Autodesk Fusion 360 part; units mm, degrees
(part 3 of 7)
  spline S81 degree 5 poles (24.1275, 16.6487) (24.1224, 16.6501) (24.1069, 16.6547) (24.0809, 16.6621) (24.0445, 16.6725) (23.9974, 16.6854) (23.9449, 16.6996) (23.8923, 16.7134) (23.8395, 16.7269) (23.7865, 16.74) (23.7335, 16.7529) (23.6803, 16.7655) (23.6269, 16.7777) (23.5735, 16.7897) (23.5199, 16.8014) (23.4662, 16.8128) (23.4124, 16.8239) (23.3585, 16.8347) (23.3045, 16.8453) (23.2503, 16.8556) (23.1961, 16.8656) (23.1417, 16.8754) (23.0873, 16.8849) (23.0327, 16.8942) (22.9781, 16.9032) (22.9234, 16.9119) (22.8685, 16.9204) (22.8136, 16.9287) (22.7586, 16.9367) (22.7034, 16.9445) (22.6482, 16.952) (22.5929, 16.9593) (22.5376, 16.9664) (22.4821, 16.9732) (22.4266, 16.9798) (22.3709, 16.9861) (22.3152, 16.9923) (22.2594, 16.9982) (22.2036, 17.0039) (22.1476, 17.0093) (22.0916, 17.0146) (22.0355, 17.0196) (21.9794, 17.0244) (21.9231, 17.029) (21.8668, 17.0334) (21.8104, 17.0375) (21.754, 17.0415) (21.6975, 17.0452) (21.6409, 17.0487) (21.5842, 17.052) (21.5275, 17.0551) (21.4707, 17.058) (21.4139, 17.0607) (21.357, 17.0632) (21.3, 17.0655) (21.243, 17.0675) (21.1973, 17.069) (21.163, 17.0701) (21.1402, 17.0707) (21.1287, 17.071) knots 0.221564 0.221564 0.221564 0.221564 0.221564 0.221564 0.228571 0.242857 0.257143 0.271429 0.285714 0.3 0.314286 0.328571 0.342857 0.357143 0.371429 0.385714 0.4 0.414286 0.428571 0.442857 0.457143 0.471429 0.485714 0.5 0.514286 0.528571 0.542857 0.557143 0.571429 0.585714 0.6 0.614286 0.628571 0.642857 0.657143 0.671429 0.685714 0.7 0.714286 0.728571 0.742857 0.757143 0.771429 0.785714 0.8 0.814286 0.828571 0.842857 0.857143 0.871429 0.885714 0.9 0.914286 0.928571 0.942857 0.957143 0.971429 0.985714 1 1 1 1 1 1
  arc A41 (21.1287, 17.071) -> (20.616, 16.0313) centre (54.5011, -0.0327) ccw
  spline S82 degree 5 poles (20.616, 16.0313) (20.6232, 16.0224) (20.6376, 16.0046) (20.6593, 15.9781) (20.6883, 15.9427) (20.7247, 15.8987) (20.7612, 15.8549) (20.7978, 15.8113) (20.8345, 15.7678) (20.8714, 15.7246) (20.9083, 15.6815) (20.9455, 15.6385) (20.9827, 15.5958) (21.0201, 15.5532) (21.0576, 15.5108) (21.0952, 15.4686) (21.1329, 15.4266) (21.1708, 15.3848) (21.2088, 15.3432) (21.2469, 15.3017) (21.2852, 15.2605) (21.3236, 15.2194) (21.3621, 15.1786) (21.4007, 15.1379) (21.4395, 15.0974) (21.4784, 15.0572) (21.5175, 15.0171) (21.5567, 14.9773) (21.596, 14.9376) (21.6354, 14.8982) (21.675, 14.859) (21.7147, 14.82) (21.7546, 14.7812) (21.7946, 14.7427) (21.8347, 14.7044) (21.875, 14.6662) (21.9154, 14.6284) (21.9559, 14.5907) (21.9966, 14.5533) (22.0375, 14.5162) (22.0784, 14.4792) (22.1196, 14.4426) (22.1608, 14.4061) (22.2023, 14.3699) (22.2438, 14.334) (22.2856, 14.2984) (22.3274, 14.263) (22.3695, 14.2279) (22.4117, 14.193) (22.454, 14.1585) (22.4965, 14.1242) (22.5392, 14.0902) (22.5821, 14.0565) (22.6251, 14.0232) (22.6682, 13.9901) (22.7072, 13.9607) (22.7376, 13.938) (22.7593, 13.922) (22.7723, 13.9124) (22.7766, 13.9093) knots -1 -1 -1 -1 -1 -1 -0.985714 -0.971429 -0.957143 -0.942857 -0.928571 -0.914286 -0.9 -0.885714 -0.871429 -0.857143 -0.842857 -0.828571 -0.814286 -0.8 -0.785714 -0.771429 -0.757143 -0.742857 -0.728571 -0.714286 -0.7 -0.685714 -0.671429 -0.657143 -0.642857 -0.628571 -0.614286 -0.6 -0.585714 -0.571429 -0.557143 -0.542857 -0.528571 -0.514286 -0.5 -0.485714 -0.471429 -0.457143 -0.442857 -0.428571 -0.414286 -0.4 -0.385714 -0.371429 -0.357143 -0.342857 -0.328571 -0.314286 -0.3 -0.285714 -0.271429 -0.257143 -0.242857 -0.228571 -0.221564 -0.221564 -0.221564 -0.221564 -0.221564 -0.221564
  spline S83 degree 3 poles (22.9417, 13.3112) (22.967, 13.3712) (22.9804, 13.4355) (22.9818, 13.5657) (22.9698, 13.6304) (22.9284, 13.7343) (22.9051, 13.775) (22.8479, 13.8489) (22.8143, 13.8817) (22.7766, 13.9093) knots 0 0 0 0 0.019532 0.019532 0.039064 0.039064 0.053081 0.053081 0.067098 0.067098 0.067098 0.067098
  arc A42 (22.9417, 13.3112) -> (22.7496, 12.8476) centre (54.5011, -0.0327) ccw
  spline S84 degree 3 poles (22.21, 12.5414) (22.2744, 12.5315) (22.34, 12.5342) (22.4666, 12.5647) (22.5263, 12.5921) (22.617, 12.6576) (22.6508, 12.6901) (22.7085, 12.7637) (22.7321, 12.8043) (22.7496, 12.8476) knots 0 0 0 0 0.019532 0.019532 0.039064 0.039064 0.053081 0.053081 0.067098 0.067098 0.067098 0.067098
  spline S85 degree 5 poles (22.21, 12.5414) (22.2048, 12.5422) (22.1888, 12.5447) (22.1621, 12.5487) (22.1246, 12.5542) (22.0762, 12.5609) (22.0223, 12.5681) (21.9683, 12.5749) (21.9142, 12.5813) (21.86, 12.5875) (21.8057, 12.5933) (21.7513, 12.5988) (21.6969, 12.604) (21.6423, 12.6089) (21.5877, 12.6135) (21.533, 12.6178) (21.4782, 12.6218) (21.4233, 12.6255) (21.3683, 12.6289) (21.3133, 12.6321) (21.2582, 12.6349) (21.2031, 12.6375) (21.1479, 12.6399) (21.0926, 12.6419) (21.0372, 12.6437) (20.9818, 12.6452) (20.9263, 12.6465) (20.8708, 12.6475) (20.8152, 12.6483) (20.7595, 12.6488) (20.7038, 12.6491) (20.648, 12.6491) (20.5922, 12.6488) (20.5363, 12.6484) (20.4804, 12.6477) (20.4244, 12.6467) (20.3684, 12.6455) (20.3123, 12.6441) (20.2562, 12.6425) (20.2, 12.6406) (20.1438, 12.6385) (20.0875, 12.6361) (20.0312, 12.6336) (19.9748, 12.6308) (19.9184, 12.6277) (19.862, 12.6245) (19.8055, 12.621) (19.749, 12.6174) (19.6924, 12.6135) (19.6358, 12.6094) (19.5792, 12.605) (19.5225, 12.6005) (19.4658, 12.5957) (19.4091, 12.5908) (19.3523, 12.5856) (19.2955, 12.5802) (19.25, 12.5757) (19.2159, 12.5723) (19.1931, 12.5699) (19.1818, 12.5687) knots 0.221564 0.221564 0.221564 0.221564 0.221564 0.221564 0.228571 0.242857 0.257143 0.271429 0.285714 0.3 0.314286 0.328571 0.342857 0.357143 0.371429 0.385714 0.4 0.414286 0.428571 0.442857 0.457143 0.471429 0.485714 0.5 0.514286 0.528571 0.542857 0.557143 0.571429 0.585714 0.6 0.614286 0.628571 0.642857 0.657143 0.671429 0.685714 0.7 0.714286 0.728571 0.742857 0.757143 0.771429 0.785714 0.8 0.814286 0.828571 0.842857 0.857143 0.871429 0.885714 0.9 0.914286 0.928571 0.942857 0.957143 0.971429 0.985714 1 1 1 1 1 1
  arc A43 (19.1818, 12.5687) -> (18.8091, 11.4709) centre (54.5011, -0.0327) ccw
  spline S86 degree 5 poles (18.8091, 11.4709) (18.8174, 11.4631) (18.834, 11.4474) (18.859, 11.4238) (18.8924, 11.3926) (18.9342, 11.3537) (18.976, 11.3151) (19.018, 11.2766) (19.0601, 11.2383) (19.1023, 11.2002) (19.1446, 11.1623) (19.187, 11.1246) (19.2295, 11.087) (19.2721, 11.0497) (19.3148, 11.0126) (19.3576, 10.9757) (19.4005, 10.9389) (19.4435, 10.9024) (19.4867, 10.8661) (19.5299, 10.83) (19.5732, 10.7941) (19.6166, 10.7584) (19.6601, 10.7229) (19.7038, 10.6876) (19.7475, 10.6526) (19.7913, 10.6178) (19.8353, 10.5832) (19.8793, 10.5488) (19.9235, 10.5146) (19.9677, 10.4807) (20.0121, 10.447) (20.0565, 10.4135) (20.1011, 10.3802) (20.1458, 10.3472) (20.1906, 10.3145) (20.2355, 10.2819) (20.2805, 10.2497) (20.3256, 10.2176) (20.3708, 10.1859) (20.4162, 10.1543) (20.4616, 10.1231) (20.5072, 10.0921) (20.5529, 10.0613) (20.5987, 10.0309) (20.6446, 10.0007) (20.6906, 9.9708) (20.7367, 9.9412) (20.783, 9.9118) (20.8294, 9.8828) (20.8759, 9.8541) (20.9225, 9.8257) (20.9692, 9.7975) (21.0161, 9.7697) (21.0631, 9.7422) (21.1102, 9.7151) (21.1527, 9.691) (21.1857, 9.6726) (21.2094, 9.6595) (21.2236, 9.6517) (21.2282, 9.6492) knots -1 -1 -1 -1 -1 -1 -0.985714 -0.971429 -0.957143 -0.942857 -0.928571 -0.914286 -0.9 -0.885714 -0.871429 -0.857143 -0.842857 -0.828571 -0.814286 -0.8 -0.785714 -0.771429 -0.757143 -0.742857 -0.728571 -0.714286 -0.7 -0.685714 -0.671429 -0.657143 -0.642857 -0.628571 -0.614286 -0.6 -0.585714 -0.571429 -0.557143 -0.542857 -0.528571 -0.514286 -0.5 -0.485714 -0.471429 -0.457143 -0.442857 -0.428571 -0.414286 -0.4 -0.385714 -0.371429 -0.357143 -0.342857 -0.328571 -0.314286 -0.3 -0.285714 -0.271429 -0.257143 -0.242857 -0.228571 -0.221564 -0.221564 -0.221564 -0.221564 -0.221564 -0.221564
  spline S87 degree 3 poles (21.4699, 9.0777) (21.4872, 9.1405) (21.4921, 9.206) (21.4765, 9.3353) (21.4561, 9.3978) (21.4016, 9.4954) (21.3732, 9.5328) (21.3068, 9.5986) (21.2692, 9.6267) (21.2282, 9.6492) knots 0 0 0 0 0.019532 0.019532 0.039064 0.039064 0.053081 0.053081 0.067098 0.067098 0.067098 0.067098
  arc A44 (21.4699, 9.0777) -> (21.3401, 8.593) centre (54.5011, -0.0327) ccw
  spline S88 degree 3 poles (20.845, 8.219) (20.9101, 8.2175) (20.9749, 8.2288) (21.0964, 8.2756) (21.152, 8.3106) (21.2333, 8.3873) (21.2627, 8.424) (21.3102, 8.5044) (21.3283, 8.5478) (21.3401, 8.593) knots 0 0 0 0 0.019532 0.019532 0.039064 0.039064 0.053081 0.053081 0.067098 0.067098 0.067098 0.067098
  spline S89 degree 5 poles (20.845, 8.219) (20.8397, 8.2191) (20.8235, 8.2195) (20.7965, 8.22) (20.7586, 8.2205) (20.7099, 8.2209) (20.6555, 8.2209) (20.601, 8.2206) (20.5465, 8.22) (20.492, 8.219) (20.4374, 8.2177) (20.3828, 8.2161) (20.3281, 8.2141) (20.2734, 8.2118) (20.2186, 8.2093) (20.1638, 8.2064) (20.1089, 8.2032) (20.054, 8.1997) (19.9991, 8.1959) (19.9442, 8.1919) (19.8892, 8.1875) (19.8341, 8.1829) (19.7791, 8.178) (19.724, 8.1728) (19.6689, 8.1673) (19.6137, 8.1616) (19.5586, 8.1557) (19.5034, 8.1494) (19.4481, 8.1429) (19.3929, 8.1361) (19.3376, 8.1291) (19.2823, 8.1219) (19.227, 8.1144) (19.1717, 8.1066) (19.1163, 8.0986) (19.0609, 8.0903) (19.0055, 8.0819) (18.9501, 8.0731) (18.8947, 8.0642) (18.8392, 8.055) (18.7838, 8.0455) (18.7283, 8.0359) (18.6728, 8.026) (18.6173, 8.0158) (18.5618, 8.0055) (18.5062, 7.9949) (18.4507, 7.9841) (18.3951, 7.9731) (18.3396, 7.9618) (18.284, 7.9504) (18.2284, 7.9387) (18.1728, 7.9268) (18.1172, 7.9147) (18.0616, 7.9023) (18.006, 7.8898) (17.9504, 7.877) (17.9059, 7.8667) (17.8725, 7.8588) (17.8502, 7.8535) (17.8391, 7.8508) knots 0.221564 0.221564 0.221564 0.221564 0.221564 0.221564 0.228571 0.242857 0.257143 0.271429 0.285714 0.3 0.314286 0.328571 0.342857 0.357143 0.371429 0.385714 0.4 0.414286 0.428571 0.442857 0.457143 0.471429 0.485714 0.5 0.514286 0.528571 0.542857 0.557143 0.571429 0.585714 0.6 0.614286 0.628571 0.642857 0.657143 0.671429 0.685714 0.7 0.714286 0.728571 0.742857 0.757143 0.771429 0.785714 0.8 0.814286 0.828571 0.842857 0.857143 0.871429 0.885714 0.9 0.914286 0.928571 0.942857 0.957143 0.971429 0.985714 1 1 1 1 1 1
  arc A45 (17.8391, 7.8508) -> (17.6129, 6.7138) centre (54.5011, -0.0327) ccw
  spline S90 degree 5 poles (17.6129, 6.7138) (17.6222, 6.7071) (17.6407, 6.6937) (17.6686, 6.6736) (17.7057, 6.647) (17.7522, 6.6139) (17.7988, 6.581) (17.8454, 6.5484) (17.8922, 6.5159) (17.939, 6.4836) (17.9859, 6.4516) (18.0328, 6.4197) (18.0799, 6.3881) (18.127, 6.3566) (18.1742, 6.3254) (18.2214, 6.2943) (18.2687, 6.2635) (18.3162, 6.2329) (18.3636, 6.2026) (18.4112, 6.1724) (18.4588, 6.1425) (18.5065, 6.1127) (18.5543, 6.0832) (18.6022, 6.054) (18.6501, 6.0249) (18.6981, 5.9961) (18.7462, 5.9675) (18.7943, 5.9392) (18.8426, 5.9111) (18.8909, 5.8832) (18.9393, 5.8556) (18.9877, 5.8282) (19.0363, 5.8011) (19.0849, 5.7742) (19.1335, 5.7475) (19.1823, 5.7211) (19.2311, 5.695) (19.2801, 5.6691) (19.329, 5.6435) (19.3781, 5.6182) (19.4273, 5.5932) (19.4765, 5.5684) (19.5258, 5.5439) (19.5751, 5.5196) (19.6246, 5.4957) (19.6741, 5.4721) (19.7237, 5.4487) (19.7734, 5.4257) (19.8232, 5.4029) (19.8731, 5.3805) (19.923, 5.3584) (19.973, 5.3367) (20.0231, 5.3152) (20.0733, 5.2941) (20.1235, 5.2733) (20.1688, 5.255) (20.204, 5.241) (20.2291, 5.2311) (20.2442, 5.2253) (20.2491, 5.2233) knots -1 -1 -1 -1 -1 -1 -0.985714 -0.971429 -0.957143 -0.942857 -0.928571 -0.914286 -0.9 -0.885714 -0.871429 -0.857143 -0.842857 -0.828571 -0.814286 -0.8 -0.785714 -0.771429 -0.757143 -0.742857 -0.728571 -0.714286 -0.7 -0.685714 -0.671429 -0.657143 -0.642857 -0.628571 -0.614286 -0.6 -0.585714 -0.571429 -0.557143 -0.542857 -0.528571 -0.514286 -0.5 -0.485714 -0.471429 -0.457143 -0.442857 -0.428571 -0.414286 -0.4 -0.385714 -0.371429 -0.357143 -0.342857 -0.328571 -0.314286 -0.3 -0.285714 -0.271429 -0.257143 -0.242857 -0.228571 -0.221564 -0.221564 -0.221564 -0.221564 -0.221564 -0.221564
  spline S91 degree 3 poles (20.5634, 4.6884) (20.5723, 4.7528) (20.5686, 4.8185) (20.5363, 4.9446) (20.5079, 5.0039) (20.4411, 5.0936) (20.408, 5.1269) (20.3337, 5.1835) (20.2927, 5.2064) (20.2491, 5.2233) knots 0 0 0 0 0.019532 0.019532 0.039064 0.039064 0.053081 0.053081 0.067098 0.067098 0.067098 0.067098
  arc A46 (20.5634, 4.6884) -> (20.4979, 4.1908) centre (54.5011, -0.0327) ccw
  spline S92 degree 3 poles (20.0559, 3.7554) (20.1206, 3.7625) (20.1833, 3.7821) (20.2977, 3.8443) (20.3483, 3.8863) (20.4189, 3.973) (20.4432, 4.0132) (20.4799, 4.0991) (20.4921, 4.1445) (20.4979, 4.1908) knots 0 0 0 0 0.019532 0.019532 0.039064 0.039064 0.053081 0.053081 0.067098 0.067098 0.067098 0.067098
  spline S93 degree 5 poles (20.0559, 3.7554) (20.0506, 3.7548) (20.0345, 3.7531) (20.0077, 3.75) (19.9701, 3.7456) (19.9216, 3.7396) (19.8677, 3.7326) (19.8138, 3.7252) (19.7598, 3.7174) (19.7059, 3.7093) (19.6519, 3.7009) (19.598, 3.6922) (19.544, 3.6831) (19.4901, 3.6737) (19.4361, 3.664) (19.3821, 3.654) (19.3282, 3.6436) (19.2742, 3.633) (19.2202, 3.6221) (19.1663, 3.6109) (19.1123, 3.5994) (19.0584, 3.5877) (19.0044, 3.5756) (18.9505, 3.5633) (18.8966, 3.5507) (18.8426, 3.5378) (18.7887, 3.5247) (18.7348, 3.5113) (18.6809, 3.4976) (18.627, 3.4837) (18.5731, 3.4696) (18.5192, 3.4551) (18.4654, 3.4405) (18.4115, 3.4256) (18.3577, 3.4104) (18.3039, 3.395) (18.25, 3.3793) (18.1962, 3.3635) (18.1425, 3.3473) (18.0887, 3.331) (18.0349, 3.3144) (17.9812, 3.2976) (17.9275, 3.2805) (17.8737, 3.2632) (17.82, 3.2457) (17.7664, 3.228) (17.7127, 3.21) (17.6591, 3.1918) (17.6054, 3.1734) (17.5518, 3.1548) (17.4983, 3.136) (17.4447, 3.1169) (17.3911, 3.0976) (17.3376, 3.0782) (17.2841, 3.0585) (17.2306, 3.0386) (17.1879, 3.0225) (17.1558, 3.0103) (17.1344, 3.0021) (17.1237, 2.9981) knots 0.221564 0.221564 0.221564 0.221564 0.221564 0.221564 0.228571 0.242857 0.257143 0.271429 0.285714 0.3 0.314286 0.328571 0.342857 0.357143 0.371429 0.385714 0.4 0.414286 0.428571 0.442857 0.457143 0.471429 0.485714 0.5 0.514286 0.528571 0.542857 0.557143 0.571429 0.585714 0.6 0.614286 0.628571 0.642857 0.657143 0.671429 0.685714 0.7 0.714286 0.728571 0.742857 0.757143 0.771429 0.785714 0.8 0.814286 0.828571 0.842857 0.857143 0.871429 0.885714 0.9 0.914286 0.928571 0.942857 0.957143 0.971429 0.985714 1 1 1 1 1 1
  arc A47 (17.1237, 2.9981) -> (17.0479, 1.8412) centre (54.5011, -0.0327) ccw
  spline S94 degree 5 poles (17.0479, 1.8412) (17.058, 1.8357) (17.0781, 1.8249) (17.1083, 1.8086) (17.1486, 1.7871) (17.199, 1.7604) (17.2495, 1.7339) (17.3, 1.7076) (17.3506, 1.6815) (17.4012, 1.6556) (17.4519, 1.6299) (17.5026, 1.6044) (17.5534, 1.5792) (17.6042, 1.5542) (17.655, 1.5294) (17.7059, 1.5048) (17.7569, 1.4804) (17.8079, 1.4563) (17.8589, 1.4323) (17.91, 1.4086) (17.9611, 1.3852) (18.0123, 1.3619) (18.0636, 1.3389) (18.1148, 1.3162) (18.1661, 1.2936) (18.2175, 1.2713) (18.2689, 1.2493) (18.3203, 1.2274) (18.3718, 1.2059) (18.4234, 1.1845) (18.4749, 1.1635) (18.5265, 1.1426) (18.5782, 1.1221) (18.6299, 1.1017) (18.6817, 1.0817) (18.7334, 1.0619) (18.7853, 1.0424) (18.8371, 1.0231) (18.889, 1.0041) (18.941, 0.9854) (18.993, 0.967) (19.045, 0.9488) (19.0971, 0.931) (19.1492, 0.9134) (19.2014, 0.8961) (19.2536, 0.8791) (19.3058, 0.8625) (19.3581, 0.8461) (19.4104, 0.8301) (19.4627, 0.8144) (19.5151, 0.799) (19.5676, 0.7839) (19.62, 0.7692) (19.6725, 0.7548) (19.7251, 0.7408) (19.7723, 0.7285) (19.809, 0.7192) (19.8353, 0.7127) (19.851, 0.7089) (19.8561, 0.7076) knots -1 -1 -1 -1 -1 -1 -0.985714 -0.971429 -0.957143 -0.942857 -0.928571 -0.914286 -0.9 -0.885714 -0.871429 -0.857143 -0.842857 -0.828571 -0.814286 -0.8 -0.785714 -0.771429 -0.757143 -0.742857 -0.728571 -0.714286 -0.7 -0.685714 -0.671429 -0.657143 -0.642857 -0.628571 -0.614286 -0.6 -0.585714 -0.571429 -0.557143 -0.542857 -0.528571 -0.514286 -0.5 -0.485714 -0.471429 -0.457143 -0.442857 -0.428571 -0.414286 -0.4 -0.385714 -0.371429 -0.357143 -0.342857 -0.328571 -0.314286 -0.3 -0.285714 -0.271429 -0.257143 -0.242857 -0.228571 -0.221564 -0.221564 -0.221564 -0.221564 -0.221564 -0.221564
  spline S95 degree 3 poles (20.2375, 0.2182) (20.238, 0.2833) (20.2257, 0.3479) (20.1772, 0.4687) (20.1413, 0.5238) (20.0634, 0.604) (20.0262, 0.6327) (19.9451, 0.6791) (19.9015, 0.6965) (19.8561, 0.7076) knots 0 0 0 0 0.019532 0.019532 0.039064 0.039064 0.053081 0.053081 0.067098 0.067098 0.067098 0.067098
  arc A48 (20.2375, 0.2182) -> (20.2375, -0.2836) centre (54.5011, -0.0327) ccw
  spline S96 degree 3 poles (19.8561, -0.773) (19.9194, -0.7576) (19.979, -0.7299) (20.0843, -0.6533) (20.129, -0.6051) (20.1876, -0.5099) (20.2065, -0.4669) (20.2316, -0.3769) (20.2378, -0.3303) (20.2375, -0.2836) knots 0 0 0 0 0.019532 0.019532 0.039064 0.039064 0.053081 0.053081 0.067098 0.067098 0.067098 0.067098
  spline S97 degree 5 poles (19.8561, -0.773) (19.851, -0.7743) (19.8353, -0.7781) (19.809, -0.7846) (19.7723, -0.7939) (19.7251, -0.8062) (19.6725, -0.8202) (19.62, -0.8346) (19.5676, -0.8493) (19.5151, -0.8644) (19.4627, -0.8798) (19.4104, -0.8955) (19.3581, -0.9115) (19.3058, -0.9279) (19.2536, -0.9445) (19.2014, -0.9615) (19.1492, -0.9788) (19.0971, -0.9964) (19.045, -1.0142) (18.993, -1.0324) (18.941, -1.0508) (18.889, -1.0695) (18.8371, -1.0885) (18.7853, -1.1078) (18.7334, -1.1273) (18.6817, -1.1471) (18.6299, -1.1671) (18.5782, -1.1875) (18.5265, -1.208) (18.4749, -1.2289) (18.4234, -1.2499) (18.3718, -1.2713) (18.3203, -1.2928) (18.2689, -1.3147) (18.2175, -1.3367) (18.1661, -1.359) (18.1148, -1.3816) (18.0636, -1.4043) (18.0123, -1.4273) (17.9611, -1.4506) (17.91, -1.474) (17.8589, -1.4977) (17.8079, -1.5217) (17.7569, -1.5458) (17.7059, -1.5702) (17.655, -1.5948) (17.6042, -1.6196) (17.5534, -1.6446) (17.5026, -1.6698) (17.4519, -1.6953) (17.4012, -1.721) (17.3506, -1.7469) (17.3, -1.773) (17.2495, -1.7993) (17.199, -1.8258) (17.1486, -1.8525) (17.1083, -1.874) (17.0781, -1.8903) (17.058, -1.9012) (17.0479, -1.9066) knots 0.221564 0.221564 0.221564 0.221564 0.221564 0.221564 0.228571 0.242857 0.257143 0.271429 0.285714 0.3 0.314286 0.328571 0.342857 0.357143 0.371429 0.385714 0.4 0.414286 0.428571 0.442857 0.457143 0.471429 0.485714 0.5 0.514286 0.528571 0.542857 0.557143 0.571429 0.585714 0.6 0.614286 0.628571 0.642857 0.657143 0.671429 0.685714 0.7 0.714286 0.728571 0.742857 0.757143 0.771429 0.785714 0.8 0.814286 0.828571 0.842857 0.857143 0.871429 0.885714 0.9 0.914286 0.928571 0.942857 0.957143 0.971429 0.985714 1 1 1 1 1 1
  arc A49 (17.0479, -1.9066) -> (17.1237, -3.0635) centre (54.5011, -0.0327) ccw
  spline S98 degree 5 poles (17.1237, -3.0635) (17.1344, -3.0675) (17.1558, -3.0757) (17.1879, -3.0879) (17.2306, -3.104) (17.2841, -3.1239) (17.3376, -3.1436) (17.3911, -3.163) (17.4447, -3.1823) (17.4983, -3.2014) (17.5518, -3.2202) (17.6054, -3.2388) (17.6591, -3.2572) (17.7127, -3.2754) (17.7664, -3.2934) (17.82, -3.3111) (17.8737, -3.3286) (17.9275, -3.3459) (17.9812, -3.363) (18.0349, -3.3798) (18.0887, -3.3964) (18.1425, -3.4127) (18.1962, -3.4289) (18.25, -3.4447) (18.3039, -3.4604) (18.3577, -3.4758) (18.4115, -3.491) (18.4654, -3.5059) (18.5192, -3.5205) (18.5731, -3.535) (18.627, -3.5491) (18.6809, -3.563) (18.7348, -3.5767) (18.7887, -3.5901) (18.8426, -3.6032) (18.8966, -3.6161) (18.9505, -3.6287) (19.0044, -3.641) (19.0584, -3.6531) (19.1123, -3.6648) (19.1663, -3.6763) (19.2202, -3.6875) (19.2742, -3.6984) (19.3282, -3.7091) (19.3821, -3.7194) (19.4361, -3.7294) (19.4901, -3.7391) (19.544, -3.7485) (19.598, -3.7576) (19.6519, -3.7663) (19.7059, -3.7747) (19.7598, -3.7828) (19.8138, -3.7906) (19.8677, -3.798) (19.9216, -3.805) (19.9701, -3.811) (20.0077, -3.8154) (20.0345, -3.8185) (20.0506, -3.8202) (20.0559, -3.8208) knots -1 -1 -1 -1 -1 -1 -0.985714 -0.971429 -0.957143 -0.942857 -0.928571 -0.914286 -0.9 -0.885714 -0.871429 -0.857143 -0.842857 -0.828571 -0.814286 -0.8 -0.785714 -0.771429 -0.757143 -0.742857 -0.728571 -0.714286 -0.7 -0.685714 -0.671429 -0.657143 -0.642857 -0.628571 -0.614286 -0.6 -0.585714 -0.571429 -0.557143 -0.542857 -0.528571 -0.514286 -0.5 -0.485714 -0.471429 -0.457143 -0.442857 -0.428571 -0.414286 -0.4 -0.385714 -0.371429 -0.357143 -0.342857 -0.328571 -0.314286 -0.3 -0.285714 -0.271429 -0.257143 -0.242857 -0.228571 -0.221564 -0.221564 -0.221564 -0.221564 -0.221564 -0.221564
  spline S99 degree 3 poles (20.4979, -4.2562) (20.4898, -4.1916) (20.4693, -4.1292) (20.4054, -4.0157) (20.3626, -3.9658) (20.2749, -3.8965) (20.2343, -3.8728) (20.1478, -3.8374) (20.1023, -3.8259) (20.0559, -3.8208) knots 0 0 0 0 0.019532 0.019532 0.039064 0.039064 0.053081 0.053081 0.067098 0.067098 0.067098 0.067098
  arc A50 (20.4979, -4.2562) -> (20.5634, -4.7538) centre (54.5011, -0.0327) ccw
  spline S100 degree 3 poles (20.2491, -5.2887) (20.3098, -5.2652) (20.3653, -5.23) (20.4597, -5.1403) (20.4977, -5.0866) (20.5435, -4.9846) (20.5565, -4.9395) (20.5697, -4.847) (20.5698, -4.8) (20.5634, -4.7538) knots 0 0 0 0 0.019532 0.019532 0.039064 0.039064 0.053081 0.053081 0.067098 0.067098 0.067098 0.067098
  spline S101 degree 5 poles (20.2491, -5.2887) (20.2442, -5.2907) (20.2291, -5.2965) (20.204, -5.3064) (20.1688, -5.3204) (20.1235, -5.3387) (20.0733, -5.3595) (20.0231, -5.3806) (19.973, -5.4021) (19.923, -5.4238) (19.8731, -5.4459) (19.8232, -5.4683) (19.7734, -5.4911) (19.7237, -5.5141) (19.6741, -5.5375) (19.6246, -5.5611) (19.5751, -5.585) (19.5258, -5.6093) (19.4765, -5.6338) (19.4273, -5.6586) (19.3781, -5.6836) (19.329, -5.709) (19.2801, -5.7346) (19.2311, -5.7604) (19.1823, -5.7865) (19.1335, -5.8129) (19.0849, -5.8396) (19.0363, -5.8665) (18.9877, -5.8936) (18.9393, -5.921) (18.8909, -5.9486) (18.8426, -5.9765) (18.7943, -6.0046) (18.7462, -6.0329) (18.6981, -6.0615) (18.6501, -6.0903) (18.6022, -6.1194) (18.5543, -6.1486) (18.5065, -6.1781) (18.4588, -6.2079) (18.4112, -6.2378) (18.3636, -6.268) (18.3162, -6.2983) (18.2687, -6.3289) (18.2214, -6.3597) (18.1742, -6.3908) (18.127, -6.422) (18.0799, -6.4535) (18.0328, -6.4851) (17.9859, -6.517) (17.939, -6.549) (17.8922, -6.5813) (17.8454, -6.6138) (17.7988, -6.6465) (17.7522, -6.6793) (17.7057, -6.7124) (17.6686, -6.739) (17.6407, -6.7591) (17.6222, -6.7725) (17.6129, -6.7792) knots 0.221564 0.221564 0.221564 0.221564 0.221564 0.221564 0.228571 0.242857 0.257143 0.271429 0.285714 0.3 0.314286 0.328571 0.342857 0.357143 0.371429 0.385714 0.4 0.414286 0.428571 0.442857 0.457143 0.471429 0.485714 0.5 0.514286 0.528571 0.542857 0.557143 0.571429 0.585714 0.6 0.614286 0.628571 0.642857 0.657143 0.671429 0.685714 0.7 0.714286 0.728571 0.742857 0.757143 0.771429 0.785714 0.8 0.814286 0.828571 0.842857 0.857143 0.871429 0.885714 0.9 0.914286 0.928571 0.942857 0.957143 0.971429 0.985714 1 1 1 1 1 1
  arc A51 (17.6129, -6.7792) -> (17.8391, -7.9162) centre (54.5011, -0.0327) ccw
  spline S102 degree 5 poles (17.8391, -7.9162) (17.8502, -7.9189) (17.8725, -7.9242) (17.9059, -7.9321) (17.9504, -7.9424) (18.006, -7.9552) (18.0616, -7.9677) (18.1172, -7.9801) (18.1728, -7.9922) (18.2284, -8.0041) (18.284, -8.0158) (18.3396, -8.0272) (18.3951, -8.0385) (18.4507, -8.0495) (18.5062, -8.0603) (18.5618, -8.0709) (18.6173, -8.0812) (18.6728, -8.0914) (18.7283, -8.1013) (18.7838, -8.1109) (18.8392, -8.1204) (18.8947, -8.1296) (18.9501, -8.1385) (19.0055, -8.1473) (19.0609, -8.1558) (19.1163, -8.164) (19.1717, -8.172) (19.227, -8.1798) (19.2823, -8.1873) (19.3376, -8.1945) (19.3929, -8.2016) (19.4481, -8.2083) (19.5034, -8.2148) (19.5586, -8.2211) (19.6137, -8.227) (19.6689, -8.2328) (19.724, -8.2382) (19.7791, -8.2434) (19.8341, -8.2483) (19.8892, -8.2529) (19.9442, -8.2573) (19.9991, -8.2613) (20.054, -8.2651) (20.1089, -8.2686) (20.1638, -8.2718) (20.2186, -8.2747) (20.2734, -8.2772) (20.3281, -8.2795) (20.3828, -8.2815) (20.4374, -8.2831) (20.492, -8.2844) (20.5465, -8.2854) (20.601, -8.286) (20.6555, -8.2863) (20.7099, -8.2863) (20.7586, -8.2859) (20.7965, -8.2854) (20.8235, -8.2849) (20.8397, -8.2845) (20.845, -8.2844) knots -1 -1 -1 -1 -1 -1 -0.985714 -0.971429 -0.957143 -0.942857 -0.928571 -0.914286 -0.9 -0.885714 -0.871429 -0.857143 -0.842857 -0.828571 -0.814286 -0.8 -0.785714 -0.771429 -0.757143 -0.742857 -0.728571 -0.714286 -0.7 -0.685714 -0.671429 -0.657143 -0.642857 -0.628571 -0.614286 -0.6 -0.585714 -0.571429 -0.557143 -0.542857 -0.528571 -0.514286 -0.5 -0.485714 -0.471429 -0.457143 -0.442857 -0.428571 -0.414286 -0.4 -0.385714 -0.371429 -0.357143 -0.342857 -0.328571 -0.314286 -0.3 -0.285714 -0.271429 -0.257143 -0.242857 -0.228571 -0.221564 -0.221564 -0.221564 -0.221564 -0.221564 -0.221564
  spline S103 degree 3 poles (21.3401, -8.6584) (21.3237, -8.5954) (21.2951, -8.5362) (21.2169, -8.432) (21.1681, -8.3881) (21.072, -8.3309) (21.0287, -8.3127) (20.9384, -8.2889) (20.8917, -8.2834) (20.845, -8.2844) knots 0 0 0 0 0.019532 0.019532 0.039064 0.039064 0.053081 0.053081 0.067098 0.067098 0.067098 0.067098
  arc A52 (21.3401, -8.6584) -> (21.4699, -9.1431) centre (54.5011, -0.0327) ccw
  spline S104 degree 3 poles (21.2282, -9.7146) (21.2853, -9.6833) (21.3358, -9.6411) (21.4176, -9.5399) (21.4483, -9.4817) (21.4804, -9.3746) (21.4874, -9.3282) (21.4884, -9.2347) (21.4824, -9.1882) (21.4699, -9.1431) knots 0 0 0 0 0.019532 0.019532 0.039064 0.039064 0.053081 0.053081 0.067098 0.067098 0.067098 0.067098
  spline S105 degree 5 poles (21.2282, -9.7146) (21.2236, -9.7171) (21.2094, -9.7249) (21.1857, -9.738) (21.1527, -9.7564) (21.1102, -9.7805) (21.0631, -9.8077) (21.0161, -9.8351) (20.9692, -9.8629) (20.9225, -9.8911) (20.8759, -9.9195) (20.8294, -9.9482) (20.783, -9.9772) (20.7367, -10.0066) (20.6906, -10.0362) (20.6446, -10.0661) (20.5987, -10.0963) (20.5529, -10.1267) (20.5072, -10.1575) (20.4616, -10.1885) (20.4162, -10.2197) (20.3708, -10.2513) (20.3256, -10.283) (20.2805, -10.3151) (20.2355, -10.3473) (20.1906, -10.3799) (20.1458, -10.4126) (20.1011, -10.4456) (20.0565, -10.4789) (20.0121, -10.5124) (19.9677, -10.5461) (19.9235, -10.58) (19.8793, -10.6142) (19.8353, -10.6486) (19.7913, -10.6832) (19.7475, -10.718) (19.7038, -10.7531) (19.6601, -10.7883) (19.6166, -10.8238) (19.5732, -10.8595) (19.5299, -10.8954) (19.4867, -10.9315) (19.4435, -10.9678) (19.4005, -11.0043) (19.3576, -11.0411) (19.3148, -11.078) (19.2721, -11.1151) (19.2295, -11.1524) (19.187, -11.19) (19.1446, -11.2277) (19.1023, -11.2656) (19.0601, -11.3037) (19.018, -11.342) (18.976, -11.3805) (18.9342, -11.4192) (18.8924, -11.458) (18.859, -11.4892) (18.834, -11.5128) (18.8174, -11.5285) (18.8091, -11.5363) knots 0.221564 0.221564 0.221564 0.221564 0.221564 0.221564 0.228571 0.242857 0.257143 0.271429 0.285714 0.3 0.314286 0.328571 0.342857 0.357143 0.371429 0.385714 0.4 0.414286 0.428571 0.442857 0.457143 0.471429 0.485714 0.5 0.514286 0.528571 0.542857 0.557143 0.571429 0.585714 0.6 0.614286 0.628571 0.642857 0.657143 0.671429 0.685714 0.7 0.714286 0.728571 0.742857 0.757143 0.771429 0.785714 0.8 0.814286 0.828571 0.842857 0.857143 0.871429 0.885714 0.9 0.914286 0.928571 0.942857 0.957143 0.971429 0.985714 1 1 1 1 1 1
  arc A53 (18.8091, -11.5363) -> (19.1818, -12.6341) centre (54.5011, -0.0327) ccw
  spline S106 degree 5 poles (19.1818, -12.6341) (19.1931, -12.6353) (19.2159, -12.6377) (19.25, -12.6411) (19.2955, -12.6456) (19.3523, -12.651) (19.4091, -12.6562) (19.4658, -12.6611) (19.5225, -12.6659) (19.5792, -12.6704) (19.6358, -12.6748) (19.6924, -12.6789) (19.749, -12.6828) (19.8055, -12.6864) (19.862, -12.6899) (19.9184, -12.6931) (19.9748, -12.6962) (20.0312, -12.699) (20.0875, -12.7015) (20.1438, -12.7039) (20.2, -12.706) (20.2562, -12.7079) (20.3123, -12.7095) (20.3684, -12.7109) (20.4244, -12.7121) (20.4804, -12.7131) (20.5363, -12.7138) (20.5922, -12.7143) (20.648, -12.7145) (20.7038, -12.7145) (20.7595, -12.7142) (20.8152, -12.7137) (20.8708, -12.7129) (20.9263, -12.7119) (20.9818, -12.7106) (21.0372, -12.7091) (21.0926, -12.7073) (21.1479, -12.7053) (21.2031, -12.7029) (21.2582, -12.7003) (21.3133, -12.6975) (21.3683, -12.6943) (21.4233, -12.6909) (21.4782, -12.6872) (21.533, -12.6832) (21.5877, -12.6789) (21.6423, -12.6743) (21.6969, -12.6694) (21.7513, -12.6642) (21.8057, -12.6587) (21.86, -12.6529) (21.9142, -12.6467) (21.9683, -12.6403) (22.0223, -12.6335) (22.0762, -12.6263) (22.1246, -12.6196) (22.1621, -12.6141) (22.1888, -12.6101) (22.2048, -12.6076) (22.21, -12.6068) knots -1 -1 -1 -1 -1 -1 -0.985714 -0.971429 -0.957143 -0.942857 -0.928571 -0.914286 -0.9 -0.885714 -0.871429 -0.857143 -0.842857 -0.828571 -0.814286 -0.8 -0.785714 -0.771429 -0.757143 -0.742857 -0.728571 -0.714286 -0.7 -0.685714 -0.671429 -0.657143 -0.642857 -0.628571 -0.614286 -0.6 -0.585714 -0.571429 -0.557143 -0.542857 -0.528571 -0.514286 -0.5 -0.485714 -0.471429 -0.457143 -0.442857 -0.428571 -0.414286 -0.4 -0.385714 -0.371429 -0.357143 -0.342857 -0.328571 -0.314286 -0.3 -0.285714 -0.271429 -0.257143 -0.242857 -0.228571 -0.221564 -0.221564 -0.221564 -0.221564 -0.221564 -0.221564
  spline S107 degree 3 poles (22.7496, -12.913) (22.7252, -12.8527) (22.6891, -12.7977) (22.598, -12.7046) (22.5438, -12.6675) (22.4411, -12.6232) (22.3958, -12.6109) (22.3031, -12.599) (22.2562, -12.5997) (22.21, -12.6068) knots 0 0 0 0 0.019532 0.019532 0.039064 0.039064 0.053081 0.053081 0.067098 0.067098 0.067098 0.067098
  arc A54 (22.7496, -12.913) -> (22.9417, -13.3766) centre (54.5011, -0.0327) ccw
  spline S108 degree 3 poles (22.7766, -13.9747) (22.8291, -13.9362) (22.8736, -13.8879) (22.9416, -13.7768) (22.9644, -13.7152) (22.9822, -13.6047) (22.9831, -13.5578) (22.9719, -13.465) (22.9599, -13.4197) (22.9417, -13.3766) knots 0 0 0 0 0.019532 0.019532 0.039064 0.039064 0.053081 0.053081 0.067098 0.067098 0.067098 0.067098
  spline S109 degree 5 poles (22.7766, -13.9747) (22.7723, -13.9778) (22.7593, -13.9874) (22.7376, -14.0035) (22.7072, -14.0261) (22.6682, -14.0555) (22.6251, -14.0886) (22.5821, -14.1219) (22.5392, -14.1556) (22.4965, -14.1896) (22.454, -14.2239) (22.4117, -14.2584) (22.3695, -14.2933) (22.3274, -14.3284) (22.2856, -14.3638) (22.2438, -14.3994) (22.2023, -14.4353) (22.1608, -14.4715) (22.1196, -14.508) (22.0784, -14.5446) (22.0375, -14.5816) (21.9966, -14.6187) (21.9559, -14.6561) (21.9154, -14.6938) (21.875, -14.7317) (21.8347, -14.7698) (21.7946, -14.8081) (21.7546, -14.8466) (21.7147, -14.8854) (21.675, -14.9244) (21.6354, -14.9636) (21.596, -15.0031) (21.5567, -15.0427) (21.5175, -15.0825) (21.4784, -15.1226) (21.4395, -15.1628) (21.4007, -15.2033) (21.3621, -15.244) (21.3236, -15.2848) (21.2852, -15.3259) (21.2469, -15.3671) (21.2088, -15.4086) (21.1708, -15.4502) (21.1329, -15.492) (21.0952, -15.534) (21.0576, -15.5762) (21.0201, -15.6186) (20.9827, -15.6612) (20.9455, -15.7039) (20.9083, -15.7469) (20.8714, -15.79) (20.8345, -15.8332) (20.7978, -15.8767) (20.7612, -15.9203) (20.7247, -15.9642) (20.6883, -16.0081) (20.6593, -16.0435) (20.6376, -16.07) (20.6232, -16.0878) (20.616, -16.0967) knots 0.221564 0.221564 0.221564 0.221564 0.221564 0.221564 0.228571 0.242857 0.257143 0.271429 0.285714 0.3 0.314286 0.328571 0.342857 0.357143 0.371429 0.385714 0.4 0.414286 0.428571 0.442857 0.457143 0.471429 0.485714 0.5 0.514286 0.528571 0.542857 0.557143 0.571429 0.585714 0.6 0.614286 0.628571 0.642857 0.657143 0.671429 0.685714 0.7 0.714286 0.728571 0.742857 0.757143 0.771429 0.785714 0.8 0.814286 0.828571 0.842857 0.857143 0.871429 0.885714 0.9 0.914286 0.928571 0.942857 0.957143 0.971429 0.985714 1 1 1 1 1 1
  arc A55 (20.616, -16.0967) -> (21.1287, -17.1364) centre (54.5011, -0.0327) ccw
  spline S110 degree 5 poles (21.1287, -17.1364) (21.1402, -17.1361) (21.163, -17.1355) (21.1973, -17.1344) (21.243, -17.1329) (21.3, -17.1309) (21.357, -17.1286) (21.4139, -17.1261) (21.4707, -17.1234) (21.5275, -17.1205) (21.5842, -17.1174) (21.6409, -17.1141) (21.6975, -17.1106) (21.754, -17.1069) (21.8104, -17.1029) (21.8668, -17.0988) (21.9231, -17.0944) (21.9794, -17.0898) (22.0355, -17.085) (22.0916, -17.08) (22.1476, -17.0747) (22.2036, -17.0693) (22.2594, -17.0636) (22.3152, -17.0577) (22.3709, -17.0515) (22.4266, -17.0452) (22.4821, -17.0386) (22.5376, -17.0318) (22.5929, -17.0247) (22.6482, -17.0174) (22.7034, -17.0099) (22.7586, -17.0021) (22.8136, -16.9941) (22.8685, -16.9858) (22.9234, -16.9773) (22.9781, -16.9686) (23.0327, -16.9596) (23.0873, -16.9503) (23.1417, -16.9408) (23.1961, -16.931) (23.2503, -16.921) (23.3045, -16.9107) (23.3585, -16.9001) (23.4124, -16.8893) (23.4662, -16.8782) (23.5199, -16.8668) (23.5735, -16.8551) (23.6269, -16.8431) (23.6803, -16.8309) (23.7335, -16.8183) (23.7865, -16.8054) (23.8395, -16.7923) (23.8923, -16.7788) (23.9449, -16.765) (23.9974, -16.7509) (24.0445, -16.7379) (24.0809, -16.7275) (24.1069, -16.7201) (24.1224, -16.7155) (24.1275, -16.7141) knots -1 -1 -1 -1 -1 -1 -0.985714 -0.971429 -0.957143 -0.942857 -0.928571 -0.914286 -0.9 -0.885714 -0.871429 -0.857143 -0.842857 -0.828571 -0.814286 -0.8 -0.785714 -0.771429 -0.757143 -0.742857 -0.728571 -0.714286 -0.7 -0.685714 -0.671429 -0.657143 -0.642857 -0.628571 -0.614286 -0.6 -0.585714 -0.571429 -0.557143 -0.542857 -0.528571 -0.514286 -0.5 -0.485714 -0.471429 -0.457143 -0.442857 -0.428571 -0.414286 -0.4 -0.385714 -0.371429 -0.357143 -0.342857 -0.328571 -0.314286 -0.3 -0.285714 -0.271429 -0.257143 -0.242857 -0.228571 -0.221564 -0.221564 -0.221564 -0.221564 -0.221564 -0.221564
  spline S111 degree 3 poles (24.7025, -16.9472) (24.6703, -16.8906) (24.6274, -16.8408) (24.525, -16.7604) (24.4664, -16.7306) (24.3588, -16.7002) (24.3123, -16.6938) (24.2188, -16.6942) (24.1724, -16.701) (24.1275, -16.7141) knots 0 0 0 0 0.019532 0.019532 0.039064 0.039064 0.053081 0.053081 0.067098 0.067098 0.067098 0.067098
  arc A56 (24.7025, -16.9472) -> (24.9534, -17.3818) centre (54.5011, -0.0327) ccw
  spline S112 degree 3 poles (24.8678, -17.9963) (24.9149, -17.9513) (24.9527, -17.8975) (25.0056, -17.7785) (25.0201, -17.7145) (25.0234, -17.6027) (25.0182, -17.556) (24.9949, -17.4655) (24.9771, -17.4221) (24.9534, -17.3818) knots 0 0 0 0 0.019532 0.019532 0.039064 0.039064 0.053081 0.053081 0.067098 0.067098 0.067098 0.067098
  spline S113 degree 5 poles (24.8678, -17.9963) (24.864, -18) (24.8523, -18.0112) (24.8328, -18.0299) (24.8057, -18.0563) (24.7709, -18.0905) (24.7324, -18.129) (24.6941, -18.1677) (24.6561, -18.2067) (24.6182, -18.2459) (24.5805, -18.2854) (24.543, -18.3252) (24.5057, -18.3653) (24.4687, -18.4056) (24.4318, -18.4461) (24.395, -18.4869) (24.3585, -18.528) (24.3222, -18.5692) (24.286, -18.6107) (24.25, -18.6525) (24.2142, -18.6944) (24.1786, -18.7366) (24.1431, -18.779) (24.1078, -18.8216) (24.0727, -18.8645) (24.0377, -18.9075) (24.003, -18.9507) (23.9683, -18.9942) (23.9339, -19.0378) (23.8996, -19.0817) (23.8655, -19.1257) (23.8315, -19.17) (23.7977, -19.2144) (23.7641, -19.259) (23.7306, -19.3038) (23.6972, -19.3488) (23.6641, -19.394) (23.6311, -19.4393) (23.5982, -19.4849) (23.5655, -19.5306) (23.533, -19.5765) (23.5006, -19.6225) (23.4683, -19.6688) (23.4362, -19.7152) (23.4043, -19.7618) (23.3725, -19.8085) (23.3409, -19.8554) (23.3094, -19.9025) (23.278, -19.9497) (23.2468, -19.9971) (23.2158, -20.0447) (23.1849, -20.0924) (23.1542, -20.1403) (23.1236, -20.1884) (23.0931, -20.2366) (23.0628, -20.2849) (23.0387, -20.3237) (23.0206, -20.3529) (23.0086, -20.3724) (23.0026, -20.3821) knots 0.221564 0.221564 0.221564 0.221564 0.221564 0.221564 0.228571 0.242857 0.257143 0.271429 0.285714 0.3 0.314286 0.328571 0.342857 0.357143 0.371429 0.385714 0.4 0.414286 0.428571 0.442857 0.457143 0.471429 0.485714 0.5 0.514286 0.528571 0.542857 0.557143 0.571429 0.585714 0.6 0.614286 0.628571 0.642857 0.657143 0.671429 0.685714 0.7 0.714286 0.728571 0.742857 0.757143 0.771429 0.785714 0.8 0.814286 0.828571 0.842857 0.857143 0.871429 0.885714 0.9 0.914286 0.928571 0.942857 0.957143 0.971429 0.985714 1 1 1 1 1 1
  arc A57 (23.0026, -20.3821) -> (23.6467, -21.3461) centre (54.5011, -0.0327) ccw
  spline S114 degree 5 poles (23.6467, -21.3461) (23.658, -21.3443) (23.6806, -21.3406) (23.7145, -21.3351) (23.7596, -21.3277) (23.8158, -21.3182) (23.872, -21.3085) (23.9281, -21.2986) (23.9841, -21.2885) (24.04, -21.2783) (24.0959, -21.2678) (24.1516, -21.2571) (24.2072, -21.2462) (24.2628, -21.2352) (24.3182, -21.2239) (24.3736, -21.2124) (24.4288, -21.2007) (24.484, -21.1888) (24.539, -21.1767) (24.594, -21.1644) (24.6489, -21.1519) (24.7036, -21.1392) (24.7582, -21.1263) (24.8128, -21.1131) (24.8672, -21.0998) (24.9215, -21.0862) (24.9757, -21.0724) (25.0298, -21.0584) (25.0838, -21.0442) (25.1377, -21.0297) (25.1914, -21.0151) (25.2451, -21.0002) (25.2986, -20.985) (25.352, -20.9697) (25.4052, -20.9541) (25.4584, -20.9383) (25.5114, -20.9222) (25.5642, -20.9059) (25.617, -20.8894) (25.6696, -20.8726) (25.7221, -20.8556) (25.7744, -20.8383) (25.8266, -20.8207) (25.8786, -20.803) (25.9305, -20.7849) (25.9823, -20.7666) (26.0338, -20.748) (26.0853, -20.7292) (26.1365, -20.7101) (26.1876, -20.6907) (26.2386, -20.671) (26.2893, -20.651) (26.3399, -20.6308) (26.3903, -20.6102) (26.4406, -20.5893) (26.4855, -20.5703) (26.5203, -20.5553) (26.5451, -20.5445) (26.5598, -20.538) (26.5647, -20.5359) knots -1 -1 -1 -1 -1 -1 -0.985714 -0.971429 -0.957143 -0.942857 -0.928571 -0.914286 -0.9 -0.885714 -0.871429 -0.857143 -0.842857 -0.828571 -0.814286 -0.8 -0.785714 -0.771429 -0.757143 -0.742857 -0.728571 -0.714286 -0.7 -0.685714 -0.671429 -0.657143 -0.642857 -0.628571 -0.614286 -0.6 -0.585714 -0.571429 -0.557143 -0.542857 -0.528571 -0.514286 -0.5 -0.485714 -0.471429 -0.457143 -0.442857 -0.428571 -0.414286 -0.4 -0.385714 -0.371429 -0.357143 -0.342857 -0.328571 -0.314286 -0.3 -0.285714 -0.271429 -0.257143 -0.242857 -0.228571 -0.221564 -0.221564 -0.221564 -0.221564 -0.221564 -0.221564
  spline S115 degree 3 poles (27.1652, -20.692) (27.1259, -20.64) (27.0769, -20.5963) (26.9648, -20.53) (26.9029, -20.5081) (26.7922, -20.4919) (26.7453, -20.4917) (26.6527, -20.5043) (26.6075, -20.5171) (26.5647, -20.5359) knots 0 0 0 0 0.019532 0.019532 0.039064 0.039064 0.053081 0.053081 0.067098 0.067098 0.067098 0.067098
  arc A58 (27.1652, -20.692) -> (27.4707, -21.0901) centre (54.5011, -0.0327) ccw
  spline S116 degree 3 poles (27.4661, -21.7105) (27.5068, -21.6598) (27.5373, -21.6015) (27.5742, -21.4767) (27.5803, -21.4112) (27.5689, -21.3) (27.5576, -21.2544) (27.5228, -21.1677) (27.4994, -21.127) (27.4707, -21.0901) knots 0 0 0 0 0.019532 0.019532 0.039064 0.039064 0.053081 0.053081 0.067098 0.067098 0.067098 0.067098
  spline S117 degree 5 poles (27.4661, -21.7105) (27.4627, -21.7147) (27.4526, -21.7273) (27.4358, -21.7484) (27.4123, -21.7781) (27.3823, -21.8166) (27.3491, -21.8597) (27.3162, -21.9031) (27.2836, -21.9467) (27.2511, -21.9906) (27.2189, -22.0347) (27.187, -22.079) (27.1552, -22.1236) (27.1237, -22.1684) (27.0924, -22.2134) (27.0614, -22.2587) (27.0305, -22.3041) (26.9999, -22.3498) (26.9694, -22.3957) (26.9392, -22.4417) (26.9092, -22.488) (26.8793, -22.5345) (26.8497, -22.5812) (26.8203, -22.628) (26.791, -22.6751) (26.762, -22.7223) (26.7332, -22.7697) (26.7045, -22.8173) (26.6761, -22.8651) (26.6478, -22.913) (26.6197, -22.9611) (26.5918, -23.0094) (26.5641, -23.0579) (26.5366, -23.1065) (26.5092, -23.1553) (26.482, -23.2042) (26.455, -23.2534) (26.4282, -23.3026) (26.4016, -23.3521) (26.3751, -23.4017) (26.3489, -23.4514) (26.3228, -23.5013) (26.2968, -23.5514) (26.2711, -23.6016) (26.2455, -23.6519) (26.2201, -23.7024) (26.1948, -23.7531) (26.1698, -23.8038) (26.1448, -23.8548) (26.1201, -23.9058) (26.0955, -23.9571) (26.0711, -24.0084) (26.0469, -24.0599) (26.0228, -24.1115) (25.9989, -24.1633) (25.9752, -24.2152) (25.9563, -24.2568) (25.9423, -24.2881) (25.9329, -24.309) (25.9282, -24.3194) knots 0.221564 0.221564 0.221564 0.221564 0.221564 0.221564 0.228571 0.242857 0.257143 0.271429 0.285714 0.3 0.314286 0.328571 0.342857 0.357143 0.371429 0.385714 0.4 0.414286 0.428571 0.442857 0.457143 0.471429 0.485714 0.5 0.514286 0.528571 0.542857 0.557143 0.571429 0.585714 0.6 0.614286 0.628571 0.642857 0.657143 0.671429 0.685714 0.7 0.714286 0.728571 0.742857 0.757143 0.771429 0.785714 0.8 0.814286 0.828571 0.842857 0.857143 0.871429 0.885714 0.9 0.914286 0.928571 0.942857 0.957143 0.971429 0.985714 1 1 1 1 1 1
  arc A59 (25.9282, -24.3194) -> (26.6926, -25.191) centre (54.5011, -0.0327) ccw
  spline S118 degree 5 poles (26.6926, -25.191) (26.7036, -25.1878) (26.7255, -25.1812) (26.7584, -25.1714) (26.8021, -25.1581) (26.8567, -25.1413) (26.9111, -25.1244) (26.9654, -25.1073) (27.0196, -25.09) (27.0737, -25.0725) (27.1277, -25.0548) (27.1816, -25.0369) (27.2353, -25.0189) (27.2889, -25.0007) (27.3424, -24.9822) (27.3958, -24.9636) (27.4491, -24.9448) (27.5022, -24.9258) (27.5552, -24.9067) (27.6081, -24.8873) (27.6609, -24.8677) (27.7135, -24.848) (27.766, -24.828) (27.8183, -24.8079) (27.8705, -24.7875) (27.9226, -24.767) (27.9746, -24.7462) (28.0264, -24.7253) (28.078, -24.7041) (28.1296, -24.6828) (28.1809, -24.6612) (28.2322, -24.6394) (28.2832, -24.6175) (28.3342, -24.5953) (28.3849, -24.5729) (28.4355, -24.5502) (28.486, -24.5274) (28.5363, -24.5043) (28.5864, -24.4811) (28.6364, -24.4576) (28.6862, -24.4338) (28.7358, -24.4099) (28.7853, -24.3857) (28.8345, -24.3613) (28.8836, -24.3366) (28.9326, -24.3117) (28.9813, -24.2865) (29.0298, -24.2611) (29.0781, -24.2355) (29.1263, -24.2096) (29.1742, -24.1834) (29.2219, -24.157) (29.2694, -24.1303) (29.3167, -24.1034) (29.3638, -24.0761) (29.4059, -24.0514) (29.4384, -24.032) (29.4616, -24.018) (29.4754, -24.0097) (29.4799, -24.0069) knots -1 -1 -1 -1 -1 -1 -0.985714 -0.971429 -0.957143 -0.942857 -0.928571 -0.914286 -0.9 -0.885714 -0.871429 -0.857143 -0.842857 -0.828571 -0.814286 -0.8 -0.785714 -0.771429 -0.757143 -0.742857 -0.728571 -0.714286 -0.7 -0.685714 -0.671429 -0.657143 -0.642857 -0.628571 -0.614286 -0.6 -0.585714 -0.571429 -0.557143 -0.542857 -0.528571 -0.514286 -0.5 -0.485714 -0.471429 -0.457143 -0.442857 -0.428571 -0.414286 -0.4 -0.385714 -0.371429 -0.357143 -0.342857 -0.328571 -0.314286 -0.3 -0.285714 -0.271429 -0.257143 -0.242857 -0.228571 -0.221564 -0.221564 -0.221564 -0.221564 -0.221564 -0.221564
  spline S119 degree 3 poles (30.0956, -24.0833) (30.0499, -24.0369) (29.9956, -23.9999) (29.8758, -23.9488) (29.8115, -23.9352) (29.6997, -23.9336) (29.6531, -23.9395) (29.563, -23.9641) (29.5198, -23.9827) (29.4799, -24.0069) knots 0 0 0 0 0.019532 0.019532 0.039064 0.039064 0.053081 0.053081 0.067098 0.067098 0.067098 0.067098
  arc A60 (30.0956, -24.0833) -> (30.4505, -24.4381) centre (54.5011, -0.0327) ccw
  spline S120 degree 3 poles (30.5269, -25.0539) (30.5607, -24.9982) (30.5833, -24.9365) (30.6036, -24.8079) (30.6011, -24.7422) (30.5752, -24.6334) (30.5581, -24.5897) (30.5123, -24.5082) (30.4838, -24.4709) (30.4505, -24.4381) knots 0 0 0 0 0.019532 0.019532 0.039064 0.039064 0.053081 0.053081 0.067098 0.067098 0.067098 0.067098
  spline S121 degree 5 poles (30.5269, -25.0539) (30.5241, -25.0584) (30.5157, -25.0722) (30.5018, -25.0954) (30.4824, -25.1279) (30.4577, -25.17) (30.4304, -25.217) (30.4035, -25.2643) (30.3768, -25.3119) (30.3503, -25.3596) (30.3242, -25.4075) (30.2983, -25.4556) (30.2726, -25.504) (30.2472, -25.5525) (30.2221, -25.6012) (30.1972, -25.6501) (30.1725, -25.6992) (30.1481, -25.7485) (30.1239, -25.798) (30.0999, -25.8476) (30.0762, -25.8974) (30.0527, -25.9473) (30.0294, -25.9975) (30.0064, -26.0478) (29.9835, -26.0982) (29.9609, -26.1488) (29.9385, -26.1996) (29.9163, -26.2505) (29.8943, -26.3016) (29.8726, -26.3528) (29.851, -26.4042) (29.8296, -26.4557) (29.8085, -26.5074) (29.7875, -26.5592) (29.7668, -26.6111) (29.7462, -26.6632) (29.7259, -26.7155) (29.7057, -26.7678) (29.6858, -26.8203) (29.666, -26.8729) (29.6465, -26.9257) (29.6271, -26.9785) (29.6079, -27.0316) (29.5889, -27.0847) (29.5701, -27.1379) (29.5515, -27.1913) (29.5331, -27.2448) (29.5149, -27.2985) (29.4968, -27.3522) (29.479, -27.4061) (29.4613, -27.46) (29.4438, -27.5141) (29.4265, -27.5684) (29.4094, -27.6227) (29.3924, -27.6771) (29.3757, -27.7317) (29.3624, -27.7754) (29.3525, -27.8082) (29.346, -27.8302) (29.3427, -27.8411) knots 0.221564 0.221564 0.221564 0.221564 0.221564 0.221564 0.228571 0.242857 0.257143 0.271429 0.285714 0.3 0.314286 0.328571 0.342857 0.357143 0.371429 0.385714 0.4 0.414286 0.428571 0.442857 0.457143 0.471429 0.485714 0.5 0.514286 0.528571 0.542857 0.557143 0.571429 0.585714 0.6 0.614286 0.628571 0.642857 0.657143 0.671429 0.685714 0.7 0.714286 0.728571 0.742857 0.757143 0.771429 0.785714 0.8 0.814286 0.828571 0.842857 0.857143 0.871429 0.885714 0.9 0.914286 0.928571 0.942857 0.957143 0.971429 0.985714 1 1 1 1 1 1
  arc A61 (29.3427, -27.8411) -> (30.2144, -28.6055) centre (54.5011, -0.0327) ccw
  spline S122 degree 5 poles (30.2144, -28.6055) (30.2248, -28.6009) (30.2457, -28.5915) (30.277, -28.5774) (30.3186, -28.5586) (30.3705, -28.5348) (30.4223, -28.5109) (30.4739, -28.4869) (30.5254, -28.4626) (30.5767, -28.4382) (30.6279, -28.4137) (30.679, -28.3889) (30.7299, -28.364) (30.7807, -28.3389) (30.8314, -28.3137) (30.8819, -28.2883) (30.9322, -28.2627) (30.9824, -28.2369) (31.0325, -28.211) (31.0824, -28.1849) (31.1321, -28.1586) (31.1817, -28.1322) (31.2311, -28.1055) (31.2804, -28.0787) (31.3295, -28.0517) (31.3785, -28.0246) (31.4273, -27.9972) (31.4759, -27.9697) (31.5244, -27.942) (31.5726, -27.9141) (31.6208, -27.886) (31.6687, -27.8577) (31.7165, -27.8293) (31.7641, -27.8006) (31.8115, -27.7718) (31.8587, -27.7427) (31.9058, -27.7135) (31.9526, -27.6841) (31.9993, -27.6544) (32.0458, -27.6246) (32.092, -27.5946) (32.1381, -27.5644) (32.184, -27.5339) (32.2296, -27.5033) (32.2751, -27.4724) (32.3203, -27.4413) (32.3654, -27.41) (32.4102, -27.3785) (32.4547, -27.3468) (32.4991, -27.3148) (32.5432, -27.2826) (32.587, -27.2502) (32.6307, -27.2175) (32.674, -27.1846) (32.7172, -27.1515) (32.7556, -27.1215) (32.7854, -27.098) (32.8065, -27.0812) (32.8191, -27.0711) (32.8232, -27.0677) knots -1 -1 -1 -1 -1 -1 -0.985714 -0.971429 -0.957143 -0.942857 -0.928571 -0.914286 -0.9 -0.885714 -0.871429 -0.857143 -0.842857 -0.828571 -0.814286 -0.8 -0.785714 -0.771429 -0.757143 -0.742857 -0.728571 -0.714286 -0.7 -0.685714 -0.671429 -0.657143 -0.642857 -0.628571 -0.614286 -0.6 -0.585714 -0.571429 -0.557143 -0.542857 -0.528571 -0.514286 -0.5 -0.485714 -0.471429 -0.457143 -0.442857 -0.428571 -0.414286 -0.4 -0.385714 -0.371429 -0.357143 -0.342857 -0.328571 -0.314286 -0.3 -0.285714 -0.271429 -0.257143 -0.242857 -0.228571 -0.221564 -0.221564 -0.221564 -0.221564 -0.221564 -0.221564
  spline S123 degree 3 poles (33.4437, -27.0631) (33.3923, -27.0231) (33.3336, -26.9935) (33.2082, -26.9584) (33.1427, -26.9533) (33.0316, -26.9664) (32.9862, -26.9783) (32.9, -27.0144) (32.8597, -27.0385) (32.8232, -27.0677) knots 0 0 0 0 0.019532 0.019532 0.039064 0.039064 0.053081 0.053081 0.067098 0.067098 0.067098 0.067098
  arc A62 (33.4437, -27.0631) -> (33.8418, -27.3686) centre (54.5011, -0.0327) ccw
  spline S124 degree 3 poles (33.9979, -27.9691) (34.0241, -27.9095) (34.0385, -27.8453) (34.0418, -27.7152) (34.0308, -27.6504) (33.991, -27.5459) (33.9683, -27.5047) (33.9122, -27.43) (33.8791, -27.3967) (33.8418, -27.3686) knots 0 0 0 0 0.019532 0.019532 0.039064 0.039064 0.053081 0.053081 0.067098 0.067098 0.067098 0.067098
  spline S125 degree 5 poles (33.9979, -27.9691) (33.9957, -27.9739) (33.9892, -27.9887) (33.9784, -28.0135) (33.9634, -28.0483) (33.9444, -28.0932) (33.9236, -28.1434) (33.903, -28.1938) (33.8828, -28.2444) (33.8628, -28.2952) (33.8431, -28.3461) (33.8237, -28.3972) (33.8046, -28.4485) (33.7857, -28.4999) (33.7672, -28.5515) (33.7488, -28.6033) (33.7308, -28.6552) (33.713, -28.7072) (33.6955, -28.7594) (33.6782, -28.8117) (33.6612, -28.8642) (33.6444, -28.9168) (33.6279, -28.9695) (33.6116, -29.0224) (33.5955, -29.0754) (33.5797, -29.1286) (33.5641, -29.1818) (33.5487, -29.2352) (33.5336, -29.2887) (33.5187, -29.3423) (33.504, -29.3961) (33.4896, -29.45) (33.4754, -29.5039) (33.4614, -29.558) (33.4476, -29.6122) (33.434, -29.6666) (33.4206, -29.721) (33.4075, -29.7755) (33.3946, -29.8302) (33.3819, -29.8849) (33.3693, -29.9398) (33.357, -29.9947) (33.3449, -30.0498) (33.3331, -30.1049) (33.3214, -30.1602) (33.3099, -30.2155) (33.2986, -30.271) (33.2875, -30.3265) (33.2767, -30.3822) (33.266, -30.4379) (33.2555, -30.4937) (33.2452, -30.5497) (33.2352, -30.6057) (33.2253, -30.6618) (33.2156, -30.7179) (33.2061, -30.7742) (33.1986, -30.8193) (33.1931, -30.8532) (33.1895, -30.8757) (33.1877, -30.887) knots 0.221564 0.221564 0.221564 0.221564 0.221564 0.221564 0.228571 0.242857 0.257143 0.271429 0.285714 0.3 0.314286 0.328571 0.342857 0.357143 0.371429 0.385714 0.4 0.414286 0.428571 0.442857 0.457143 0.471429 0.485714 0.5 0.514286 0.528571 0.542857 0.557143 0.571429 0.585714 0.6 0.614286 0.628571 0.642857 0.657143 0.671429 0.685714 0.7 0.714286 0.728571 0.742857 0.757143 0.771429 0.785714 0.8 0.814286 0.828571 0.842857 0.857143 0.871429 0.885714 0.9 0.914286 0.928571 0.942857 0.957143 0.971429 0.985714 1 1 1 1 1 1
  arc A63 (33.1877, -30.887) -> (34.1517, -31.5311) centre (54.5011, -0.0327) ccw